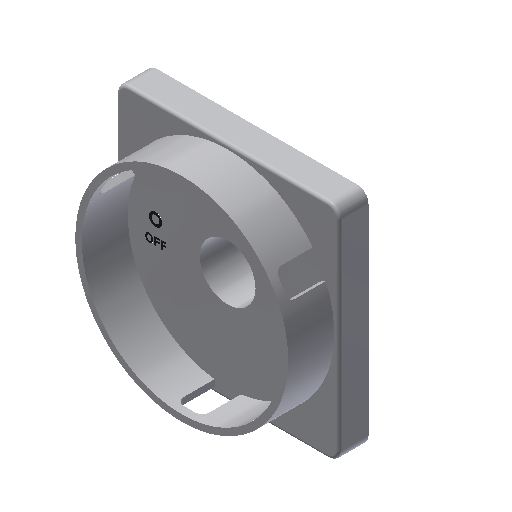
# Autodesk Inventor part: BASE DA CHAVE
Saved by Autodesk Inventor 2022.2 (Build 262287010, 287A)
## iProperties
Created: 2020-03-18
Part Number: BASE DA CHAVE
Material: Plástico, preto opaco
Document SubType Name: Modeling
Designer: Projeto
Density: 0.952 g/cm^3
Appearance: Preto moldado(1)
Mass: 46.7925 g
Surface Area: 207.217 cm^2
Volume: 49.1518 cm^3
Author: Projeto
Autodesk Inventor part; units mm, degrees
ref_plane "YZ Plane" through (0, 0, 0) normal (1, 0, 0) x (0, 1, 0)
ref_plane "XZ Plane" through (0, 0, 0) normal (0, 1, 0) x (-1, 0, 0)
ref_plane "XY Plane" through (0, 0, 0) normal (0, 0, 1) x (1, 0, 0)
sketch "Esboço1" plane through (0, 0, 0) normal (0, 0, 1) x (1, 0, 0)
  line L0 (30.5, -34) -> (-30.5, -34)
  line L1 (-34, -30.5) -> (-34, 30.5)
  line L2 (-30.5, 34) -> (30.5, 34)
  line L3 (34, 30.5) -> (34, -30.5)
  line L4 (34, -34) -> (-34, 34) construction
  line L5 (-34, -34) -> (34, 34) construction
  arc A0 (-30.5, 34) -> (-34, 30.5) centre (-30.5, 30.5) ccw
  arc A1 (34, 30.5) -> (30.5, 34) centre (30.5, 30.5) ccw
  arc A2 (30.5, -34) -> (34, -30.5) centre (30.5, -30.5) ccw
  arc A3 (-34, -30.5) -> (-30.5, -34) centre (-30.5, -30.5) ccw
  point P0 (0, 0)
  dimension "d0" = 68
  dimension "d1" = 3.5
  constraints: 12 end point, 8 point on circle, 8 point on line, 8 tangent, 4 centre point, 3 equal radius, 2 midpoint, 2 parallel, 2 perpendicular, 1 horizontal
  measures "d0" distance of L4.end L5.end
  measures "d1" radius of A0
extrude "Extrusão1" add sketch "Esboço1" along normal blind 9
sketch "Esboço2" plane through (0, 0, 0) normal (1, 0, 0) x (0, 1, 0)
  line L0 (0, 9) -> (0, -11.2763)
  line L1 (0, -11.2763) -> (9.25, -22.3)
  line L2 (9.25, -22.3) -> (10, -22.3)
  line L3 (10, -22.3) -> (10, -17.3)
  line L4 (10.125, -13.3) -> (10.9, -12.8526)
  line L5 (10.9, -12.8526) -> (10.9, -8.6)
  line L6 (10.9, -8.6) -> (12.35, -8.6)
  line L7 (12.35, -8.6) -> (12.35, -8.1)
  line L8 (12.35, -8.1) -> (13.5, -8)
  line L9 (13.5, -8) -> (13.5, -7.6)
  line L10 (13.5, -7.6) -> (14.25, -7.6)
  line L11 (14.25, -7.6) -> (14.25, -4.6)
  line L12 (14.25, -4.6) -> (14.5, -4.6)
  line L13 (14.5, -4.6) -> (14.5, -2.6)
  line L14 (14.5, -2.6) -> (10.9, -2.6)
  line L15 (10.9, -2.6) -> (10.9, -1)
  line L16 (10.9, -1) -> (14.75, -1)
  line L17 (14.75, -1) -> (14.75, 8)
  line L18 (14.75, 8) -> (32.5, 8)
  line L19 (32.5, 8) -> (32.5, 23)
  line L20 (32.5, 23) -> (30.5, 23)
  line L21 (30.5, 23) -> (30.5, 9)
  line L22 (30.5, 9) -> (0, 9)
  line L23 (30.5, 9) -> (-30.5, 9) projected
  line L24 (10, -17.3) -> (10.125, -15.3)
  line L25 (10.125, -15.3) -> (10.125, -13.3)
  point P0 (0, 0)
  point P1 (15.25, 9)
  dimension "d4" = 65
  dimension "d5" = 61
  dimension "d6" = 1
  dimension "d7" = 14
  dimension "d8" = 29.5
  dimension "d9" = 21.8
  dimension "d10" = 29
  dimension "d11" = 24.7
  dimension "d12" = 27
  dimension "d13" = 28.5
  dimension "d14" = 20.25
  dimension "d15" = 20
  dimension "d16" = 18.5
  dimension "d18" = 50
  dimension "d19" = 5
  dimension "d20" = 7
  dimension "d21" = 9
  dimension "d22" = 60
  dimension "d23" = 13.7
  dimension "d24" = 6
  dimension "d25" = 0.5
  dimension "d26" = 1
  dimension "d27" = 0.6
  dimension "d28" = 2
  dimension "d29" = 9
  dimension "d30" = 21.3
  constraints: 50 end point, 15 perpendicular, 4 point on line, 2 parallel, 2 vertical, 1 horizontal, 1 midpoint
  measures "d4" diameter of L19 L0
  measures "d5" diameter of L21 L0
  measures "d6" distance between parallel lines of L18 L23
  measures "d7" distance between parallel lines of L22 L20
  measures "d8" diameter of L17 L0
  measures "d9" diameter of L5 L0
  measures "d10" diameter of L13 L0
  measures "d11" diameter of L7 L0
  measures "d12" diameter of L9 L0
  measures "d13" diameter of L11 L0
  measures "d14" diameter of L25 L0
  measures "d15" diameter of L3 L0
  measures "d16" diameter of L1.end L0
  measures "d18" angle of L1 L2
  measures "d19" distance of L2.end L3.end
  measures "d20" distance from line of L24.end L2
  measures "d21" distance from line of L4.start L2
  measures "d22" angle of L25 L4
  measures "d23" distance between parallel lines of L6 L2
  measures "d24" distance between parallel lines of L14 L6
  measures "d25" distance from line of L7.end L6
  measures "d26" distance between parallel lines of L6 L10
  measures "d27" distance from line of L8.end L6
  measures "d28" distance of L12.end L13.end
  measures "d29" distance between parallel lines of L18 L16
  measures "d30" distance between parallel lines of L2 L16
revolve "Revolução1" add sketch "Esboço2" angle 360 about axis through (0, 0, 9) along (0, 0, -1)
hole "Furo1" at (0, 0, 9) direction (0, 0, -1) diameter 10 end through all counterbore diameter 17 counterbore depth 24.3
sketch "Esboço3" plane through (-30.5, -34, 0) normal (0, -1, 0) x (1, 0, 0)
  line L0 (0, 9) -> (61, 9) projected
  line L1 (26.5, 9) -> (34.5, 9)
  line L2 (34.5, 9) -> (34.5, 18.5)
  arc A0 (34.5, 18.5) -> (32.5, 20.5) centre (32.5, 18.5) ccw
  line L3 (32.5, 20.5) -> (28.5, 20.5)
  arc A1 (28.5, 20.5) -> (26.5, 18.5) centre (28.5, 18.5) ccw
  line L4 (26.5, 18.5) -> (26.5, 9)
  line L5 (0, 0) -> (61, 0) projected
  point P0 (30.5, 0)
  point P1 (30.5, 20.5)
  point P2 (30.5, 0)
  dimension "d43" = 8
  dimension "d44" = 11.5
  dimension "d45" = 2
  constraints: 8 end point, 4 point on circle, 4 tangent, 2 centre point, 2 midpoint, 2 perpendicular, 2 point on line, 1 equal radius, 1 vertical, 1 vertical alignment
  measures "d43" distance between parallel lines of L4 L2
  measures "d44" distance between parallel lines of L0 L3
  measures "d45" radius of A1
extrude "Extrusão2" cut sketch "Esboço3" against normal blind 10
pattern_circular "Padrão circular1" count 3 over 360 about axis through (0, 0, -10) along (0, 0, 1) of "Extrusão2"
fillet "Arredondamento1" radius 1 8 edges at (32.9749, 32.9749, 9) (0, 34, 9) (-32.9749, 32.9749, 9) (-34, 0, 9) (-32.9749, -32.9749, 9) (0, -34, 9) (32.9749, -32.9749, 9) (34, 0, 9)
sketch "Esboço4" plane through (0, 0, 9) normal (0, 0, 1) x (1, 0, 0)
  circle A0 centre (-22, 3) radius 2
  circle A1 centre (-22, 3) radius 1.2
  line L0 (-0.4, 26.5) -> (0.4, 26.5)
  line L1 (0.4, 26.5) -> (0.4, 22.5)
  line L2 (0.4, 22.5) -> (-0.4, 22.5)
  line L3 (-0.4, 22.5) -> (-0.4, 26.5)
  line L4 (-2.5, 20) -> (2.5, 20) construction
  line L5 (2.5, 20) -> (2.5, 17.5) construction
  line L6 (2.5, 17.5) -> (-2.5, 17.5) construction
  line L7 (-2.5, 17.5) -> (-2.5, 20) construction
  line L8 (-25.25, -1.5) -> (-18.75, -1.5) construction
  line L9 (-18.75, -1.5) -> (-18.75, -4) construction
  line L10 (-18.75, -4) -> (-25.25, -4) construction
  line L11 (-25.25, -4) -> (-25.25, -1.5) construction
  spline S0 degree 2 poles (0.0344, 18.6973) (0.0344, 18.0895) (-0.6139, 17.3947) (-1.1771, 17.3947) knots 0 0 0 1 2 2 2
  spline S1 degree 2 poles (-1.1771, 17.3947) (-1.7423, 17.3947) (-2.3865, 18.0977) (-2.3865, 18.6973) knots 0 0 0 1 2 2 2
  spline S2 degree 2 poles (-2.3865, 18.6973) (-2.3865, 19.299) (-1.7423, 20) (-1.1771, 20) knots 0 0 0 1 2 2 2
  spline S3 degree 2 poles (-1.1771, 20) (-0.6139, 20) (0.0344, 19.3031) (0.0344, 18.6973) knots 0 0 0 1 2 2 2
  spline S4 degree 2 poles (-0.6139, 18.6973) (-0.6139, 18.9222) (-0.705, 19.2362) (-0.784, 19.3355) knots 0 0 0 1 2 2 2
  spline S5 degree 2 poles (-0.784, 19.3355) (-0.863, 19.4388) (-1.0656, 19.528) (-1.175, 19.528) knots 0 0 0 1 2 2 2
  spline S6 degree 2 poles (-1.175, 19.528) (-1.2905, 19.528) (-1.4789, 19.4449) (-1.566, 19.3395) knots 0 0 0 1 2 2 2
  spline S7 degree 2 poles (-1.566, 19.3395) (-1.643, 19.2423) (-1.7382, 18.9202) (-1.7382, 18.6973) knots 0 0 0 1 2 2 2
  spline S8 degree 2 poles (-1.7382, 18.6973) (-1.7382, 18.4664) (-1.6471, 18.1625) (-1.5681, 18.0592) knots 0 0 0 1 2 2 2
  spline S9 degree 2 poles (-1.5681, 18.0592) (-1.4891, 17.9558) (-1.2844, 17.8667) (-1.175, 17.8667) knots 0 0 0 1 2 2 2
  spline S10 degree 2 poles (-1.175, 17.8667) (-1.0636, 17.8667) (-0.857, 17.9619) (-0.782, 18.0632) knots 0 0 0 1 2 2 2
  spline S11 degree 2 poles (-0.782, 18.0632) (-0.701, 18.1726) (-0.6139, 18.4623) (-0.6139, 18.6973) knots 0 0 0 1 2 2 2
  line L12 (2.5486, 17.4473) -> (1.9449, 17.4473)
  line L13 (1.9449, 17.4473) -> (0.9806, 19.1896)
  line L14 (0.9806, 19.1896) -> (0.9806, 17.4473)
  line L15 (0.9806, 17.4473) -> (0.4072, 17.4473)
  line L16 (0.4072, 17.4473) -> (0.4072, 19.9473)
  line L17 (0.4072, 19.9473) -> (1.1771, 19.9473)
  line L18 (1.1771, 19.9473) -> (1.9753, 18.515)
  line L19 (1.9753, 18.515) -> (1.9753, 19.9473)
  line L20 (1.9753, 19.9473) -> (2.5486, 19.9473)
  line L21 (2.5486, 19.9473) -> (2.5486, 17.4473)
  spline S12 degree 2 poles (-22.7156, -2.8027) (-22.7156, -3.4105) (-23.3639, -4.1053) (-23.9271, -4.1053) knots 0 0 0 1 2 2 2
  spline S13 degree 2 poles (-23.9271, -4.1053) (-24.4923, -4.1053) (-25.1365, -3.4023) (-25.1365, -2.8027) knots 0 0 0 1 2 2 2
  spline S14 degree 2 poles (-25.1365, -2.8027) (-25.1365, -2.201) (-24.4923, -1.5) (-23.9271, -1.5) knots 0 0 0 1 2 2 2
  spline S15 degree 2 poles (-23.9271, -1.5) (-23.3639, -1.5) (-22.7156, -2.1969) (-22.7156, -2.8027) knots 0 0 0 1 2 2 2
  spline S16 degree 2 poles (-23.3639, -2.8027) (-23.3639, -2.5778) (-23.455, -2.2638) (-23.534, -2.1645) knots 0 0 0 1 2 2 2
  spline S17 degree 2 poles (-23.534, -2.1645) (-23.613, -2.0612) (-23.8156, -1.972) (-23.925, -1.972) knots 0 0 0 1 2 2 2
  spline S18 degree 2 poles (-23.925, -1.972) (-24.0405, -1.972) (-24.2289, -2.0551) (-24.316, -2.1605) knots 0 0 0 1 2 2 2
  spline S19 degree 2 poles (-24.316, -2.1605) (-24.393, -2.2577) (-24.4882, -2.5798) (-24.4882, -2.8027) knots 0 0 0 1 2 2 2
  spline S20 degree 2 poles (-24.4882, -2.8027) (-24.4882, -3.0336) (-24.3971, -3.3375) (-24.3181, -3.4408) knots 0 0 0 1 2 2 2
  spline S21 degree 2 poles (-24.3181, -3.4408) (-24.2391, -3.5442) (-24.0344, -3.6333) (-23.925, -3.6333) knots 0 0 0 1 2 2 2
  spline S22 degree 2 poles (-23.925, -3.6333) (-23.8136, -3.6333) (-23.607, -3.5381) (-23.532, -3.4368) knots 0 0 0 1 2 2 2
  spline S23 degree 2 poles (-23.532, -3.4368) (-23.451, -3.3274) (-23.3639, -3.0377) (-23.3639, -2.8027) knots 0 0 0 1 2 2 2
  line L22 (-20.6694, -2.0288) -> (-21.7188, -2.0288)
  line L23 (-21.7188, -2.0288) -> (-21.7188, -2.5008)
  line L24 (-21.7188, -2.5008) -> (-20.7524, -2.5008)
  line L25 (-20.7524, -2.5008) -> (-20.7524, -2.9769)
  line L26 (-20.7524, -2.9769) -> (-21.7188, -2.9769)
  line L27 (-21.7188, -2.9769) -> (-21.7188, -4.0527)
  line L28 (-21.7188, -4.0527) -> (-22.3428, -4.0527)
  line L29 (-22.3428, -4.0527) -> (-22.3428, -1.5527)
  line L30 (-22.3428, -1.5527) -> (-20.6694, -1.5527)
  line L31 (-20.6694, -1.5527) -> (-20.6694, -2.0288)
  line L32 (-18.6718, -2.0288) -> (-19.7212, -2.0288)
  line L33 (-19.7212, -2.0288) -> (-19.7212, -2.5008)
  line L34 (-19.7212, -2.5008) -> (-18.7549, -2.5008)
  line L35 (-18.7549, -2.5008) -> (-18.7549, -2.9769)
  line L36 (-18.7549, -2.9769) -> (-19.7212, -2.9769)
  line L37 (-19.7212, -2.9769) -> (-19.7212, -4.0527)
  line L38 (-19.7212, -4.0527) -> (-20.3452, -4.0527)
  line L39 (-20.3452, -4.0527) -> (-20.3452, -1.5527)
  line L40 (-20.3452, -1.5527) -> (-18.6718, -1.5527)
  line L41 (-18.6718, -1.5527) -> (-18.6718, -2.0288)
  point P0 (0, 0)
  point P1 (0, 22.5)
  point P2 (0, 20)
  point P3 (-22, -1.5)
  dimension "d53" = 0.8
  dimension "d54" = 2.4
  dimension "d55" = 3
  dimension "d56" = 22
  dimension "d57" = 4
  dimension "d58" = 0.8
  dimension "d59" = 22.5
  dimension "d60" = 5
  dimension "d61" = 2.5
  dimension "d62" = 2.5
  dimension "d63" = 2.5
  dimension "d64" = 6.5
  dimension "d65" = 1.5
  constraints: 8 end point, 3 midpoint, 3 vertical alignment, 2 centre point, 2 horizontal, 2 parallel, 1 coincident, 1 perpendicular, 4 other
  measures "d53" radial gap between concentric circles of A0 A1
  measures "d54" diameter of A1
  measures "d55" vertical distance of A0.centre point (0, 0)
  measures "d56" horizontal distance of A0.centre point (0, 0)
  measures "d57" distance of L2.end L0.start
  measures "d58" distance of L0.start L0.end
  measures "d59" distance from line of point (0, 0) L2
  measures "d60" distance of L5.end L6.end
  measures "d61" distance of L4.end L5.end
  measures "d62" distance between parallel lines of L2 L4
  measures "d63" distance of L10.end L8.start
  measures "d64" distance of L8.start L8.end
  measures "d65" distance from line of point (0, 0) L8
extrude "Extrusão3" add sketch "Esboço4" along normal blind 0.001
sketch "Esboço5" plane through (0, 0, -7.6) normal (0, 0, -1) x (-1, 0, 0)
  circle A0 centre (0, 0) radius 14.25 construction
  arc A1 (0.2, 14.2486) -> (-0.2, 14.2486) centre (0, 14.229) ccw
  arc A2 (0.2, 14.2486) -> (-0.2, 14.2486) centre (0, 0) ccw
  point P0 (0, 0)
  dimension "d70" = 0.4
  dimension "d72" = 0.18
  constraints: 6 point on circle, 2 centre point, 1 coincident, 1 concentric, 1 vertical alignment
  measures "d70" distance of A0.end A0.start
extrude "Extrusão4" add sketch "Esboço5" against normal up to surface (3 mm away)
pattern_circular "Padrão circular2" count 95 over 360 about axis through (0, 0, -10) along (0, 0, 1) of "Extrusão4"
sketch "Esboço6" plane through (0, 0, -8.6) normal (0, 0, -1) x (-1, 0, 0)
  circle A0 centre (0, 0) radius 12.35 projected
  line L0 (-2, 12.187) -> (-2, 15.687)
  line L1 (-2, 15.687) -> (2, 15.687)
  line L2 (2, 15.687) -> (2, 12.187)
  arc A1 (2, 12.187) -> (-2, 12.187) centre (0, 0) ccw
  point P0 (0, 0)
  point P1 (0, 15.687)
  dimension "d82" = 4
  dimension "d83" = 3.5
  constraints: 6 end point, 4 point on circle, 2 perpendicular, 1 centre point, 1 concentric, 1 midpoint, 1 vertical, 1 vertical alignment
  measures "d82" distance of L0.end L1.end
  measures "d83" distance from line of L0.start L1
extrude "Extrusão5" cut sketch "Esboço6" against normal up to surface (4 mm away) contours A0 L0 L1 L2
pattern_circular "Padrão circular3" count 6 over 360 about axis through (0, 0, -10) along (0, 0, 1) of "Extrusão5"
thread "Rosca1" size "M22x0.5" class "6g" standard "ANSI Metric M Profile" full length
thread "Rosca2" size "M22x0.5" class "6g" standard "ANSI Metric M Profile" full length
sketch "Esboço7" plane through (0, 0, -22.3) normal (0, 0, -1) x (-1, 0, 0)
  line L0 (-2.2, -10) -> (2.2, -10) construction
  line L1 (2.2, -10) -> (2.2, 10)
  line L2 (2.2, 10) -> (-2.2, 10) construction
  line L3 (-2.2, 10) -> (-2.2, -10)
  line L4 (-2.2, -10) -> (2.2, 10) construction
  line L5 (2.2, -10) -> (-2.2, 10) construction
  arc A0 (2.2, 7.8994) -> (-2.2, 7.8994) centre (0, 0) ccw
  arc A1 (-2.2, -7.8994) -> (2.2, -7.8994) centre (0, 0) ccw
  dimension "d94" = 4.4
  dimension "d95" = 20
  dimension "d96" = 16.4
  constraints: 12 end point, 4 point on circle, 4 point on line, 2 centre point, 2 equal length, 2 midpoint, 1 coincident, 1 concentric, 1 parallel, 1 vertical
  measures "d94" distance of L1.end L2.end
  measures "d95" distance of L0.end L1.end
  measures "d96" diameter of A1
extrude "Extrusão6" cut sketch "Esboço7" against normal blind 10
sketch "Esboço8" plane through (0, 0, -22.3) normal (0, 0, -1) x (-1, 0, 0)
  arc A0 (2.25, 10.6652) -> (-2.25, 10.6652) centre (0, 0) ccw
  arc A1 (-2.25, -10.6652) -> (2.25, -10.6652) centre (0, 0) ccw
  arc A2 (2.25, 9.7436) -> (-2.25, 9.7436) centre (0, 0) ccw
  arc A3 (-2.25, -9.7436) -> (2.25, -9.7436) centre (0, 0) ccw
  circle A4 centre (0, 0) radius 10 construction
  circle A5 centre (0, 0) radius 10.9 construction
  line L0 (2.25, 10.6652) -> (2.25, 9.7436)
  line L1 (2.25, -9.7436) -> (2.25, -10.6652)
  line L2 (-2.25, 10.6652) -> (-2.25, 9.7436)
  line L3 (-2.25, -9.7436) -> (-2.25, -10.6652)
  line L4 (10.25, 3.7078) -> (10.25, -3.7078)
  line L5 (-10.25, -3.7078) -> (-10.25, 3.7078)
  arc A6 (10.25, -3.7078) -> (10.25, 3.7078) centre (0, 0) ccw
  arc A7 (-10.25, 3.7078) -> (-10.25, -3.7078) centre (0, 0) ccw
  point P0 (2.25, 10.2044)
  point P1 (2.25, -10.2044)
  point P2 (-2.25, -10.2044)
  point P3 (-2.25, 10.2044)
  dimension "d99" = 4.5
  dimension "d100" = 2.25
  dimension "d101" = 10.25
  dimension "d102" = 20.5
  constraints: 22 point on circle, 12 end point, 8 concentric, 6 centre point, 5 vertical, 4 midpoint, 2 point on line, 2 vertical alignment, 1 parallel
  measures "d99" distance between parallel lines of L2 L0
  measures "d100" distance from line of L0 point (0, 0)
  measures "d101" distance from line of point (0, 0) L4
  measures "d102" distance between parallel lines of L5 L4
extrude "Extrusão7" cut sketch "Esboço8" against normal up to surface (22.3 mm away)
